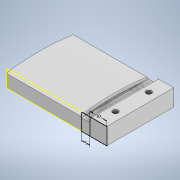
# Autodesk Inventor part: dedesubt
Saved by Autodesk Inventor 2022.6 (Build 266554000, 554)
## iProperties
Created: 2026-06-26
Part Number: dedesubt
Material: Generic
Document SubType Name: Modeling
Designer: Dragos Macovei
Density: 1 g/cm^3
Appearance: Default
Author: Dragos Macovei
Autodesk Inventor part; units mm, degrees
ref_plane "YZ Plane" through (0, 0, 0) normal (1, 0, 0) x (0, 1, 0)
ref_plane "XZ Plane" through (0, 0, 0) normal (0, 1, 0) x (-1, 0, 0)
ref_plane "XY Plane" through (0, 0, 0) normal (0, 0, 1) x (1, 0, 0)
sketch "Sketch4" plane through (0, 0, 0) normal (0, 1, 0) x (-1, 0, 0)
  line L0 (0, 0) -> (60, 0)
  line L1 (60, 0) -> (60, 40)
  line L2 (60, 40) -> (0, 40)
  line L3 (0, 40) -> (0, 0)
  dimension "d11" = 60
  dimension "d12" = 40
  constraints: 8 end point, 2 parallel, 1 horizontal, 1 perpendicular
  measures "d11" distance of L2.end L1.end
  measures "d12" distance of L1.end L0.end
extrude "Extrusion3" add sketch "Sketch4" along normal blind 10
sketch "Sketch5" plane through (-60, 0, 40) normal (0, 0, 1) x (1, 0, 0)
  line L0 (0, 0) -> (60, 0) projected
  line L1 (60, 0) -> (60, 10) projected
  line L2 (0, 10) -> (60, 10) projected
  line L3 (0, 0) -> (0, 10) projected
  line L4 (0, 0) -> (60, 0) projected
  line L5 (0, 10) -> (60, 10) projected
  line L6 (60, 0) -> (50, 0)
  line L7 (50, 0) -> (50, 10)
  line L8 (50, 10) -> (60, 10)
  line L9 (60, 10) -> (60, 0)
  line L10 (50, 10) -> (45, 10)
  line L11 (45, 10) -> (45, 0)
  line L12 (45, 0) -> (50, 0)
  line L13 (50, 0) -> (50, 10)
  dimension "d15" = 10
  dimension "d16" = 5
  constraints: 16 end point, 4 parallel, 2 horizontal, 2 perpendicular, 2 point on line
  measures "d15" distance of L7.end L8.end
  measures "d16" distance of L12.end L11.end
sketch "Sketch6" plane through (-60, 0, 0) normal (-1, 0, 0) x (0, 0, 1)
  line L0 (0, 0) -> (40, 0) projected
  line L1 (40, 0) -> (40, 10) projected
  line L2 (0, 10) -> (40, 10) projected
  line L3 (0, 0) -> (0, 10) projected
  circle A0 centre (20, -126) radius 135
  line L4 (0, 10) -> (40, 10) projected
  point P0 (20, 10)
  point P1 (40, 7.5103)
  point P2 (0, 7.5103)
  dimension "d17" = 270
  dimension "d25" = 136
  constraints: 1 centre point
  measures "d17" diameter of A0
  measures "d25" distance from line of L2 A0.centre
extrude "Extrusion4" cut sketch "Sketch6" against normal blind 45 contours L3 L2 L1 A0
sketch "Sketch7" plane through (0, 10, 0) normal (0, 1, 0) x (1, 0, 0)
  line L0 (-15, 0) -> (-15, -40) projected
  line L1 (-15, -40) -> (0, -40) projected
  line L2 (0, -40) -> (0, 0) projected
  line L3 (0, 0) -> (-15, 0) projected
  line L4 (0, 0) -> (-60, 0) projected
  line L5 (-15, -40) -> (-10, -40)
  line L6 (-10, -40) -> (-10, 0)
  line L7 (-10, 0) -> (-15, 0)
  line L8 (-15, 0) -> (-15, -40)
  dimension "d20" = 5
  constraints: 8 end point, 2 parallel, 1 horizontal, 1 perpendicular, 1 point on line
  measures "d20" distance of L7.end L6.end
extrude "Extrusion5" cut sketch "Sketch7" against normal blind 3 contours L3 L6 L1 L0
fillet "Fillet2" radius 1 2 edges at (-10, 7, 20) (-10, 10, 20)
sketch "Sketch8" plane through (0, 0, 0) normal (0, -1, 0) x (1, 0, 0)
  line L0 (-60, 0) -> (-60, 40) projected
  line L1 (0, 0) -> (-60, 0) projected
  line L2 (0, 40) -> (0, 0) projected
  line L3 (-60, 40) -> (0, 40) projected
  line L4 (0, 0) -> (-60, 0) projected
  line L5 (0, 40) -> (-10, 40)
  line L6 (-10, 40) -> (-10, 0)
  line L7 (-10, 0) -> (0, 0)
  line L8 (0, 0) -> (0, 40)
  line L9 (-9, 40) -> (0, 40) construction
  line L10 (-5, 40) -> (-5.1489, -0.4974)
  line L11 (-5.0269, 32.6834) -> (-2.4929, 31.208)
  line L12 (-2.4929, 31.208) -> (-2.5037, 28.2758)
  line L13 (-2.5037, 28.2758) -> (-5.0485, 26.819)
  line L14 (-5.0485, 26.819) -> (-7.5824, 28.2945)
  line L15 (-7.5824, 28.2945) -> (-7.5717, 31.2267)
  line L16 (-7.5717, 31.2267) -> (-5.0269, 32.6834)
  line L17 (-5.1004, 12.6831) -> (-2.5668, 11.2079)
  line L18 (-2.5668, 11.2079) -> (-2.5776, 8.2762)
  line L19 (-2.5776, 8.2762) -> (-5.122, 6.8196)
  line L20 (-5.122, 6.8196) -> (-7.6555, 8.2948)
  line L21 (-7.6555, 8.2948) -> (-7.6448, 11.2266)
  line L22 (-7.6448, 11.2266) -> (-5.1004, 12.6831)
  point P0 (-5, 0)
  point P1 (-5.0744, 19.7513)
  point P2 (-5.1112, 9.7514)
  point P3 (-5.0377, 29.7512)
  point P4 (-5.0377, 29.7512)
  point P5 (-5.1112, 9.7514)
  point P6 (-6.3888, 7.5572)
  dimension "d28" = 10
  dimension "d29" = 10
  constraints: 34 end point, 6 point on line, 3 midpoint, 2 coincident, 2 parallel, 1 horizontal, 1 perpendicular, 26 other
  measures "d28" distance of point (-5.074, 19.751) point (-5.111, 9.751)
  measures "d29" distance of point (-5.074, 19.751) point (-5.038, 29.751)
extrude "Extrusion6" cut sketch "Sketch8" against normal blind 4 contours L20 L21 L22 L10 | L10 L17 L18 L19 | L11 L12 L13 L10 | L10 L14 L15 L16
sketch "Sketch9" plane through (0, 0, 0) normal (0, -1, 0) x (1, 0, 0)
  line L0 (-5.1004, 12.6831) -> (-2.5668, 11.2079) projected
  line L1 (-7.6448, 11.2266) -> (-5.1004, 12.6831) projected
  line L2 (-7.6555, 8.2948) -> (-7.6448, 11.2266) projected
  line L3 (-5.122, 6.8196) -> (-7.6555, 8.2948) projected
  line L4 (-2.5776, 8.2762) -> (-5.122, 6.8196) projected
  line L5 (-2.5668, 11.2079) -> (-2.5776, 8.2762) projected
  line L6 (-5.0269, 32.6834) -> (-2.4929, 31.208) projected
  line L7 (-7.5717, 31.2267) -> (-5.0269, 32.6834) projected
  line L8 (-7.5824, 28.2945) -> (-7.5717, 31.2267) projected
  line L9 (-5.0485, 26.819) -> (-7.5824, 28.2945) projected
  line L10 (-2.5037, 28.2758) -> (-5.0485, 26.819) projected
  line L11 (-2.4929, 31.208) -> (-2.5037, 28.2758) projected
  circle A0 centre (-5.122, 9.7524) radius 1.6
  circle A1 centre (-5.0485, 29.7606) radius 1.6
  point P0 (0, 0)
  point P1 (-5.0485, 9.742)
  dimension "d34" = 3.2
  dimension "d35" = 3.2
  constraints: 2 centre point, 1 coincident
  measures "d34" diameter of A0
  measures "d35" diameter of A1
extrude "Extrusion7" cut sketch "Sketch9" against normal through all contours A0 | A1
fillet "Fillet3" radius 1 1 edges at (-15, 9, 20)
body "Solid3"
